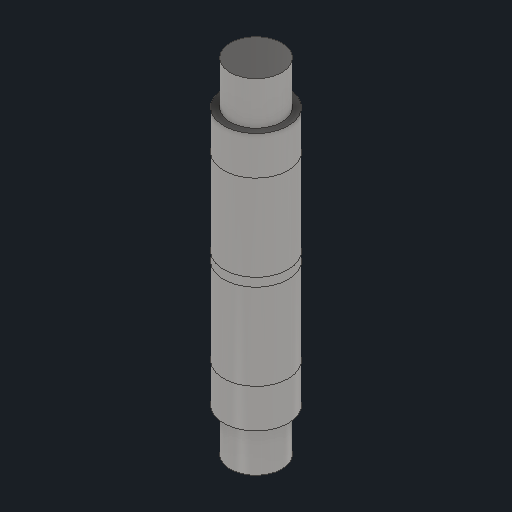
# Autodesk Inventor part: E2
Saved by Autodesk Inventor 2027 (Build 310192000, 192)
## iProperties
Created: 2026-11-10
Part Number: E2
Material: Genérico
Description: Eixo E2
Document SubType Name: Modeling
Designer: Bruno Madela
Mass: 12.8648 g
Surface Area: 39.3484 cm^2
Volume: 12.8648 cm^3
Density: 1 g/cm^3
Appearance: Aço - Polido
Author: Bruno Madela
Autodesk Inventor part; units mm, degrees
sketch "Esboço1" plane through (0, 0, 0) normal (0, 0, 1) x (1, 0, 0)
  line L0 (0, 0) -> (6, 0)
  line L1 (6, 0) -> (6, 10)
  line L2 (6, 10) -> (7.5, 10)
  line L3 (7.5, 10) -> (7.5, 19)
  line L4 (7.5, 19) -> (7.5, 39)
  line L5 (7.5, 39) -> (7.5, 41)
  line L6 (7.5, 41) -> (7.5, 61)
  line L7 (7.5, 61) -> (7.5, 70)
  line L8 (7.5, 70) -> (6, 70)
  line L9 (6, 70) -> (6, 80)
  line L10 (6, 80) -> (0, 80)
  line L11 (0, 80) -> (0, 0)
  constraints: 24 end point
revolve "Eixo E2 (revolucao 80 mm)" add sketch "Esboço1" angle 360 about axis through (0, 80, 0) along (0, -1, 0)
ref_plane "Plano_divisao_19" through (0, 19, 0) normal (0, 1, 0) x (-1, 0, 0)
split_face "Divisao_trecho_19"
ref_plane "Plano_divisao_39" through (0, 39, 0) normal (0, 1, 0) x (-1, 0, 0)
split_face "Divisao_trecho_39"
ref_plane "Plano_divisao_41" through (0, 41, 0) normal (0, 1, 0) x (-1, 0, 0)
split_face "Divisao_trecho_41"
ref_plane "Plano_divisao_61" through (0, 61, 0) normal (0, 1, 0) x (-1, 0, 0)
split_face "Divisao_trecho_61"
